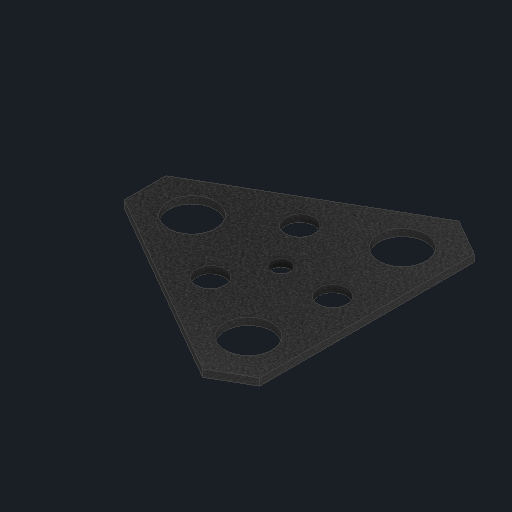
# Autodesk Inventor part: tripod_tray
Saved by Autodesk Inventor 2027.1 (Build 311270010, 270A)
## iProperties
Created: 2026-11-04
Part Number: tripod_tray
Material: Generic
Description: Accessory tray: 3x 1.25 in + 3x small eyepiece holes
Document SubType Name: Modeling
Designer: Claude (from photos)
Density: 1 g/cm^3
Appearance: Black Cast
Author: alexg
Autodesk Inventor part; units mm, degrees
ref_plane "YZ Plane" through (0, 0, 0) normal (1, 0, 0) x (0, 1, 0)
ref_plane "Work Plane1" through (0, -242, 0) normal (0, 1, 0) x (-1, 0, 0)
sketch "Tray plate sketch" plane through (0, -242, 0) normal (0, 1, 0) x (-1, 0, 0)
  line L0 (-60, -74.8246) -> (-34.8, -89.3738)
  line L1 (-34.8, -89.3738) -> (94.8, -14.5492)
  line L2 (94.8, -14.5492) -> (94.8, 14.5492)
  line L3 (94.8, 14.5492) -> (-34.8, 89.3738)
  line L4 (-34.8, 89.3738) -> (-60, 74.8246)
  line L5 (-60, 74.8246) -> (-60, -74.8246)
  constraints: 12 end point
extrude "Tray plate" add sketch "Tray plate sketch" along normal blind 5
ref_plane "Work Plane2" through (0, -244, 0) normal (0, 1, 0) x (-1, 0, 0)
sketch "Eyepiece holes sketch" plane through (0, -244, 0) normal (0, 1, 0) x (-1, 0, 0)
  circle A0 centre (-31, -53.6936) radius 16.5
  circle A1 centre (-36, 0) radius 10
  circle A2 centre (62, 0) radius 16.5
  circle A3 centre (18, -31.1769) radius 10
  circle A4 centre (-31, 53.6936) radius 16.5
  circle A5 centre (18, 31.1769) radius 10
  circle A6 centre (0, 0) radius 6.5
  constraints: 7 centre point
extrude "Eyepiece holes" cut sketch "Eyepiece holes sketch" along normal blind 10
body "Solid1"
